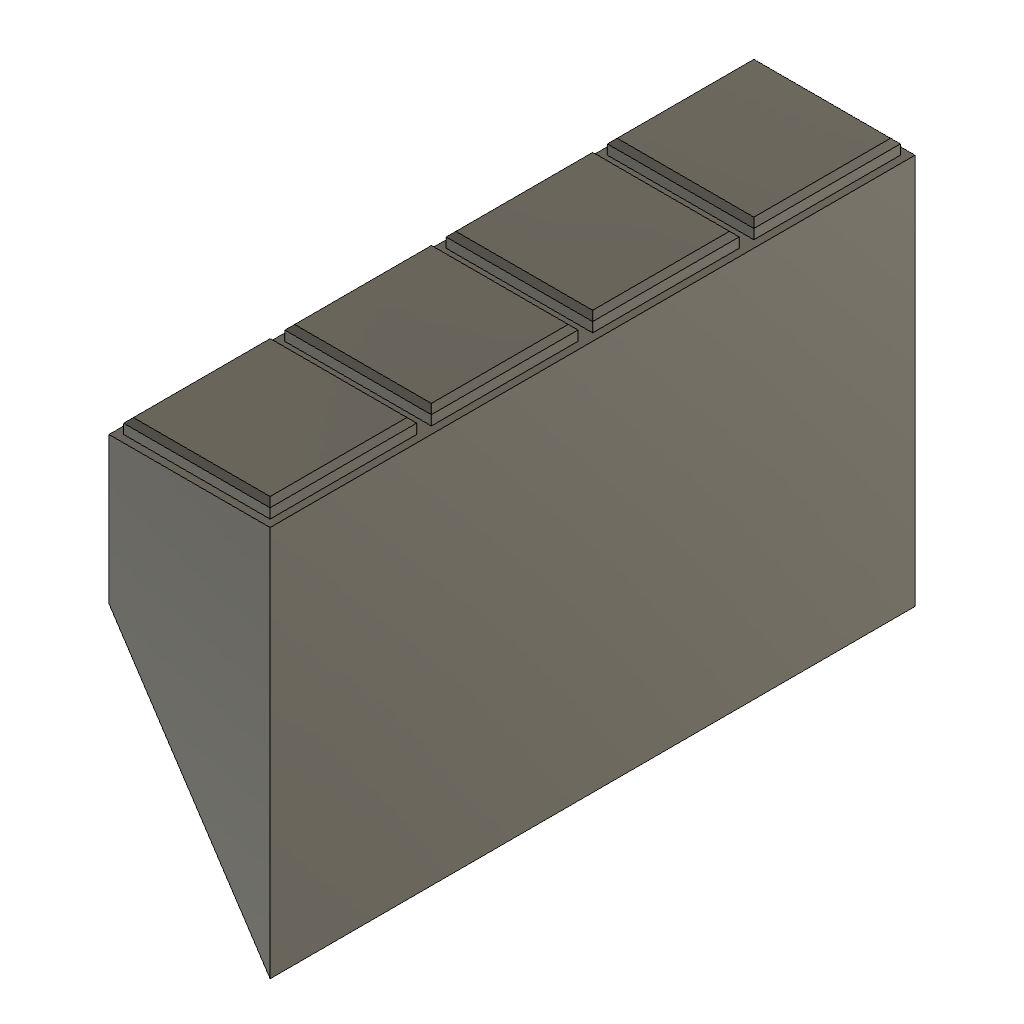
Notes Compartment (Autodesk Fusion 360 design; units mm, degrees)
part number: 2026-10-19-02-33-09-776
Autodesk Fusion 360 part; units mm, degrees
sketch "Sketch1" plane through (0, 0, 0) normal (0, 1, 0) x (1, 0, 0)
  line L0 (0, 0) -> (-33, 0)
  line L1 (-33, 0) -> (-33, 30)
  line L2 (0, 80) -> (0, 0)
  line L3 (-33, 30) -> (0, 80)
  dimension "d2" = 33
  constraint horizontal L0
  constraint vertical L1
  constraint vertical L2
  constraint coincident L0.start L2.end
  measures "d2" distance of L1 L2
extrude "Extrude1" add sketch "Sketch1" along normal blind 132
sketch "Sketch2" plane through (0, 0, 0) normal (0, 0, 1) x (-1, 0, 0)
  line L0 (33, 0) -> (0, 0)
  line L1 (0, 0) -> (0, -132)
  line L2 (0, -132) -> (33, -132)
  line L3 (33, -132) -> (33, 0)
  line L4 (0, 0) -> (33, 0)
  line L5 (33, 0) -> (33, -132)
  line L6 (33, -132) -> (0, -132)
  line L7 (0, -132) -> (0, 0)
  line L8 (3, -3) -> (30, -3)
  line L9 (30, -3) -> (30, -129)
  line L10 (30, -129) -> (3, -129)
  line L11 (3, -129) -> (3, -3)
  dimension "d5" = 3
  dimension "d6" = 3
  dimension "d7" = 3
  dimension "d8" = 3
  constraint horizontal L4
  constraint vertical L5
  constraint horizontal L6
  constraint vertical L7
  constraint coincident L2.end L3.start
  constraint coincident L0.end L1.start
  constraint horizontal L8
  constraint vertical L9
  constraint horizontal L10
  constraint vertical L11
  measures "d5" distance of L4 L8
  measures "d6" distance of L7 L11
  measures "d7" distance of L5 L9
  measures "d8" distance of L6 L10
extrude "Extrude2" cut sketch "Sketch2" against normal blind 80 contours L8 L9 L10 L11
sketch "Sketch3" plane through (0, 0, 0) normal (0, 0, 1) x (1, 0, 0)
  line L0 (-33, 132) -> (0, 132)
  line L1 (0, 132) -> (0, 0)
  line L2 (0, 0) -> (-33, 0)
  line L3 (-33, 0) -> (-33, 132)
  constraint horizontal L0
  constraint vertical L1
  constraint horizontal L2
  constraint vertical L3
  constraint coincident L1.end L2.start
extrude "Extrude3" add sketch "Sketch3" against normal blind 3
sketch "Sketch4" plane through (0, 0, 0) normal (0, 0, 1) x (1, 0, 0)
  line L0 (-33, 0) -> (0, 0)
  line L1 (0, 0) -> (0, 132)
  line L2 (0, 132) -> (-33, 132)
  line L3 (-33, 132) -> (-33, 0)
  line L4 (-1.5, 130.5) -> (-31.5, 130.5)
  line L5 (-31.5, 130.5) -> (-31.5, 100.5)
  line L6 (-31.5, 100.5) -> (-1.5, 100.5)
  line L7 (-1.5, 100.5) -> (-1.5, 130.5)
  line L8 (-1.5, 97.5) -> (-31.5, 97.5)
  line L9 (-31.5, 97.5) -> (-31.5, 67.5)
  line L10 (-31.5, 67.5) -> (-1.5, 67.5)
  line L11 (-1.5, 67.5) -> (-1.5, 97.5)
  line L12 (-1.5, 64.5) -> (-31.5, 64.5)
  line L13 (-31.5, 64.5) -> (-31.5, 34.5)
  line L14 (-31.5, 34.5) -> (-1.5, 34.5)
  line L15 (-1.5, 34.5) -> (-1.5, 64.5)
  line L16 (-1.5, 31.5) -> (-31.5, 31.5)
  line L17 (-31.5, 31.5) -> (-31.5, 1.5)
  line L18 (-31.5, 1.5) -> (-1.5, 1.5)
  line L19 (-1.5, 1.5) -> (-1.5, 31.5)
  dimension "d13" = 132
  dimension "d14" = 33
  dimension "d15" = 1.5
  dimension "d16" = 1.5
  dimension "d17" = 1.5
  dimension "d18" = 1.5
  dimension "d19" = 1.5
  dimension "d20" = 1.5
  dimension "d21" = 1.5
  dimension "d22" = 1.5
  dimension "d23" = 1.5
  dimension "d24" = 1.5
  dimension "d25" = 3
  dimension "d26" = 3
  dimension "d27" = 3
  dimension "d28" = 30
  dimension "d29" = 30
  dimension "d30" = 30
  constraint horizontal L0
  constraint vertical L1
  constraint horizontal L2
  constraint vertical L3
  constraint horizontal L4
  constraint vertical L5
  constraint horizontal L6
  constraint vertical L7
  constraint horizontal L8
  constraint vertical L9
  constraint horizontal L10
  constraint vertical L11
  constraint horizontal L12
  constraint vertical L13
  constraint horizontal L14
  constraint vertical L15
  constraint horizontal L16
  constraint vertical L17
  constraint horizontal L18
  constraint vertical L19
  measures "d13" distance of L0 L2
  measures "d14" distance of L1 L3
  measures "d15" distance of L1 L7
  measures "d16" distance of L2 L4
  measures "d17" distance of L3 L5
  measures "d18" distance of L1 L11
  measures "d19" distance of L3 L9
  measures "d20" distance of L1 L15
  measures "d21" distance of L3 L13
  measures "d22" distance of L1 L19
  measures "d23" distance of L3 L17
  measures "d24" distance of L0 L18
  measures "d25" distance of L6 L8
  measures "d26" distance of L10 L12
  measures "d27" distance of L14 L16
  measures "d28" distance of L4 L6
  measures "d29" distance of L8 L10
  measures "d30" distance of L16 L18
extrude "Extrude4" add sketch "Sketch4" along normal blind 3 contours L4 L5 L6 L7 | L8 L9 L10 L11 | L12 L13 L14 L15 | L16 L17 L18 L19
chamfer "Chamfer1" distance 1 angle 45 4 faces at (-21.5, 120.5, 3) (-21.5, 87.5, 3) (-21.5, 44.5, 3) (-21.5, 21.5, 3) tangent chain off
fillet "Fillet1" radius 1 1 edges at (-3, 129, -39.2273)
fillet "Fillet2" radius 1 1 edges at (-3, 3, -39.2273)
fillet "Fillet3" radius 1 1 edges at (-30, 3, -18.7727)
fillet "Fillet4" radius 1 1 edges at (-30, 129, -18.7727)
